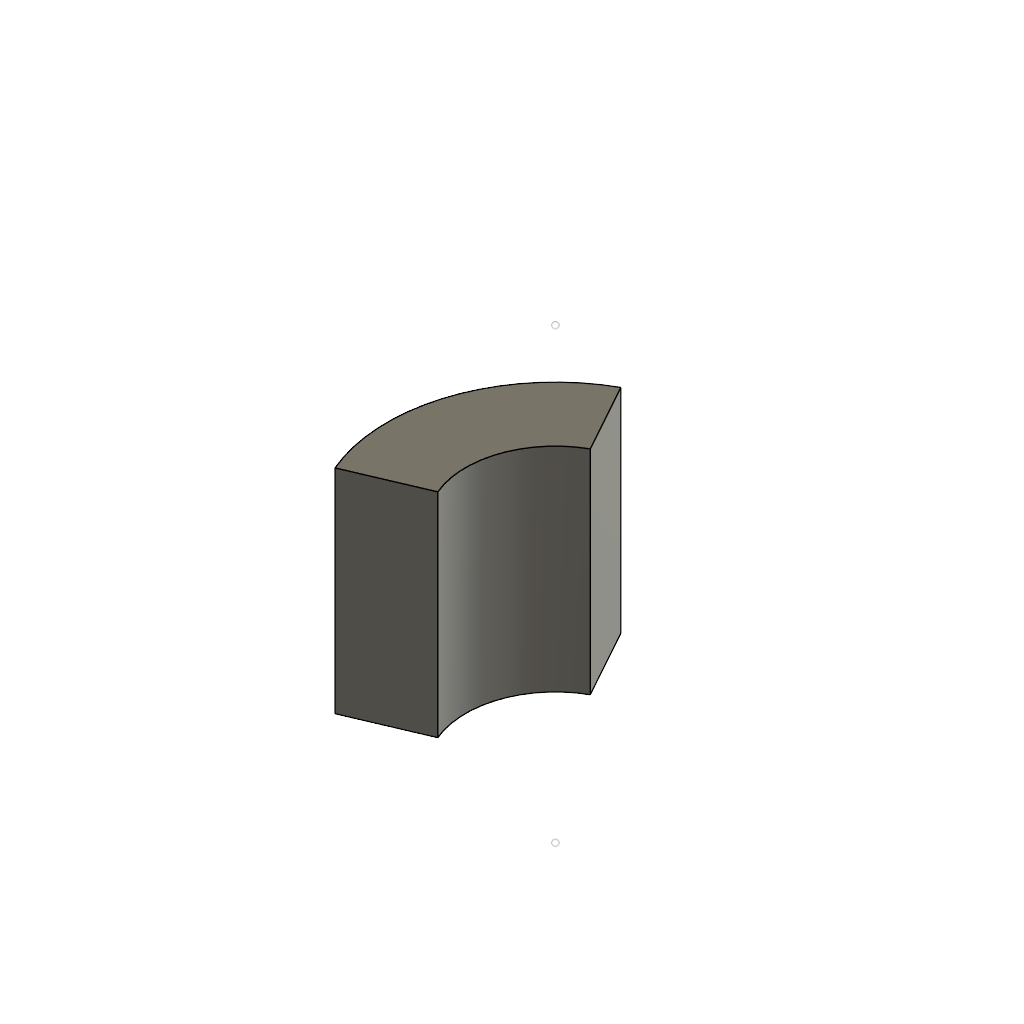
swapped_restored (Autodesk Fusion 360 design; units mm, degrees)
part number: 2026-11-27-16-03-29-423
Autodesk Fusion 360 part; units mm, degrees
sketch "AxisSupport" plane through (0, 0, 0) normal (0, 0, 1) x (1, 0, 0)
  point P0 (11, -7)
  point P1 (11, 33)
sketch "RevolveProfile" plane through (0, 0, 0) normal (0, 0, 1) x (1, 0, 0)
  line L0 (3, -1) -> (3, 18)
  line L1 (3, 18) -> (-4, 18)
  line L2 (-4, 18) -> (-4, -1)
  line L3 (-4, -1) -> (3, -1)
revolve "UnequalRevolve" add sketch "RevolveProfile" angle 23 about axis through (11, -15, 0) along (0, 1, 0) second angle 61
